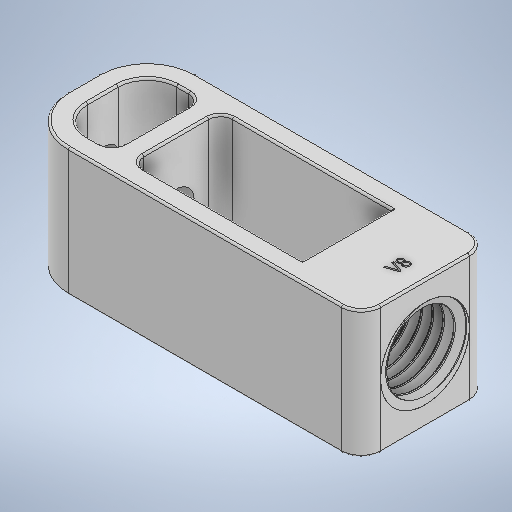
# Autodesk Inventor part: water_release_V6_noncompliant
Saved by Autodesk Inventor 2025.2 (Build 292293000, 293)
## iProperties
Created: 2025-09-30
Part Number: water_release_V6_noncompliant
Material: Generic
Document SubType Name: Modeling
Designer: Eden Salzig
Density: 1 g/cm^3
Appearance: Default
Author: Eden Salzig
Autodesk Inventor part; units mm, degrees
ref_plane "YZ Plane" through (0, 0, 0) normal (1, 0, 0) x (0, 1, 0)
ref_plane "XZ Plane" through (0, 0, 0) normal (0, 1, 0) x (-1, 0, 0)
ref_plane "XY Plane" through (0, 0, 0) normal (0, 0, 1) x (1, 0, 0)
sketch "Sketch1" plane through (0, 0, 0) normal (0, 1, 0) x (-1, 0, 0)
  line L0 (44.45, 0) -> (44.45, -23.114)
  line L1 (49.53, 0) -> (49.53, -23.114)
  arc A0 (55.88, -28.194) -> (68.58, -15.494) centre (55.88, -15.494) ccw
  line L2 (68.58, -7.62) -> (68.58, -15.494)
  arc A1 (68.58, -7.62) -> (55.88, 5.08) centre (55.88, -7.62) ccw
  line L3 (0, 0) -> (49.53, 0)
  line L4 (49.53, -23.114) -> (0, -23.114)
  line L5 (55.88, 5.08) -> (-20.32, 5.08)
  line L6 (-20.32, -28.194) -> (55.88, -28.194)
  line L7 (-20.32, 5.08) -> (-20.32, -28.194)
  line L8 (68.58, -11.557) -> (-20.32, -11.557) construction
  line L9 (0, 0) -> (0, -23.114)
  line L10 (63.5, -15.494) -> (63.5, -7.62)
  line L11 (49.53, -23.114) -> (55.88, -23.114)
  line L12 (49.53, 0) -> (55.88, 0)
  arc A2 (55.88, -23.114) -> (63.5, -15.494) centre (55.88, -15.494) ccw
  arc A3 (63.5, -7.62) -> (55.88, 0) centre (55.88, -7.62) ccw
  dimension "d1" = 24.13
  dimension "d2" = 5.08
  dimension "d3" = 12.7
  dimension "d4" = 12.7
  dimension "d5" = 23.114
  dimension "d6" = 5.08
  dimension "d7" = 5.08
  dimension "d8" = 20.32
  dimension "d63" = 69.85
  dimension "d90" = 5.08
  constraints: 27 end point, 8 point on circle, 6 tangent, 4 centre point, 4 horizontal, 2 horizontal alignment, 2 midpoint, 2 parallel, 2 point on line, 2 vertical, 2 vertical alignment, 1 coincident
  measures "d1" distance between parallel lines of L2 L0
  measures "d2" distance between parallel lines of L1 L0
  measures "d3" radius of A0
  measures "d4" radius of A1
  measures "d5" distance of L9.start L9.end
  measures "d6" distance between parallel lines of L6 L4
  measures "d7" distance between parallel lines of L5 L3
  measures "d8" distance between parallel lines of L7 L9
  measures "d63" distance between parallel lines of L1 L7
  measures "d90" distance between parallel lines of L10 L2
extrude "Extrusion1" add sketch "Sketch1" along normal blind 33.274 contours L3 L1 L4 L0 | L6 L7 L5 A1 L2 A0
sketch "Sketch2" plane through (20.32, 0, 5.08) normal (1, 0, 0) x (0, 0, -1)
  circle A0 centre (16.637, 16.637) radius 11.557
  line L0 (0, 0) -> (0, 33.274) projected
  line L1 (0, 0) -> (33.274, 0) projected
  point P0 (5.08, 0)
  dimension "d12" = 23.114
  dimension "d13" = 16.637
  dimension "d14" = 16.637
  constraints: 1 centre point
  measures "d12" diameter of A0
  measures "d13" distance from line of L0 A0.centre
  measures "d14" distance from line of L1 A0.centre
extrude "Extrusion2" cut sketch "Sketch2" against normal blind 20.32
sketch "Sketch5" plane through (-68.58, 0, -15.494) normal (-1, 0, 0) x (0, 0, 1)
  circle A0 centre (3.937, 16.637) radius 4.699
  line L0 (0, 33.274) -> (7.874, 33.274) projected
  line L1 (-12.7, 0) -> (-12.7, 33.274) projected
  point P0 (15.494, 0)
  point P1 (-12.7, 16.637)
  dimension "d39" = 9.398
  dimension "d40" = 16.637
  dimension "d41" = 16.637
  constraints: 1 centre point, 1 midpoint
  measures "d39" diameter of A0
  measures "d40" distance from line of L0 A0.centre
  measures "d41" distance of point (-12.7, 16.637) A0.centre
extrude "Extrusion3" cut sketch "Sketch5" against normal blind 25.4
fillet "Fillet2" radius 3.175 4 edges at (-44.45, 16.637, 0) (-44.45, 16.637, -23.114) (-49.53, 16.637, 0) (-49.53, 16.637, -23.114)
fillet "Fillet2" radius 5.08 2 edges at (20.32, 16.637, 5.08) (20.32, 16.637, -28.194)
thread "Thread7" size "15/16-9 UNC" class "2B" standard "ANSI Unified Screw Threads" length 20.32
sketch "Sketch17" plane through (0, 16.637, -11.557) normal (0, 1, 0) x (0, 0, 1)
  line L0 (11.557, 0) -> (11.557, 20.32)
  line L1 (11.557, 20.32) -> (9.4644, 20.32)
  line L2 (9.4644, 20.32) -> (9.4644, 0)
  line L3 (9.4644, 0) -> (11.557, 0)
  line L4 (0, -86.3628) -> (0, 38.1005) projected
  constraints: 8 end point
revolve "Revolution7" add sketch "Sketch17" angle 360 about axis through (0, 16.637, -11.557) along (1, 0, 0) separate body
sketch "Sketch16" plane through (0, 16.637, 0) normal (0, -1, 0) x (1, 0, 0)
  line L0 (-1.6464, -0.1429) -> (-1.4112, -0.1429) construction
  line L1 (0.2351, -1.95) -> (-0.0001, -2.4018) construction
  line L2 (-2.8223, -2.4018) -> (-3.0575, -1.95) construction
  line L3 (-1.176, -0.1429) -> (-1.4112, 0.3089) construction
  line L4 (-1.4112, 0.3089) -> (-1.6464, -0.1429) construction
  line L5 (-2.8223, -2.4018) -> (-2.5871, -1.95) construction
  line L6 (-1.176, -0.1429) -> (-0.2353, -1.95)
  line L7 (-3.0575, -1.95) -> (-2.5871, -1.95) construction
  arc A0 (-3.0575, -1.95) -> (-2.8223, -2.0927) centre (-2.8223, -1.8276) ccw construction
  line L8 (0.2351, -1.95) -> (-0.2353, -1.95) construction
  line L9 (-2.8223, -2.4018) -> (-2.8223, -1.95) construction
  line L10 (-0.0001, -2.4018) -> (-0.0001, -1.95) construction
  line L11 (-1.4112, 0.3089) -> (-1.4112, -0.0002) construction
  line L12 (-2.8223, -2.0927) -> (-0.0001, -2.0927)
  arc A1 (-2.8223, -2.0927) -> (-2.5871, -1.95) centre (-2.8223, -1.8276) ccw
  line L13 (-0.2353, -1.95) -> (-0.0001, -2.4018) construction
  line L14 (-2.5871, -1.95) -> (-1.6464, -0.1429)
  line L15 (-0.0001, -0.0002) -> (-0.0001, 0.0177)
  line L16 (-0.0001, 0.0177) -> (-0.0001, -0.0002)
  line L17 (-0.0001, -0.0002) -> (0.0334, -0.0002)
  arc A2 (-0.2353, -1.95) -> (-0.0001, -2.0927) centre (-0.0001, -1.8276) ccw
  arc A3 (-0.0001, -2.0927) -> (0.2351, -1.95) centre (-0.0001, -1.8276) ccw construction
  arc A4 (-1.4112, -0.0002) -> (-1.6464, -0.1429) centre (-1.4112, -0.2653) ccw
  arc A5 (-1.176, -0.1429) -> (-1.4112, -0.0002) centre (-1.4112, -0.2653) ccw
  line L18 (-1.4112, -0.0002) -> (-1.4112, -0.1429) construction
  line L19 (-1.4112, -0.1429) -> (-1.176, -0.1429) construction
  dimension "d151" = 55
  dimension "d152" = 0.4518
  dimension "d153" = 0.4518
  dimension "Sketch16_ThreadOffset" = 0
  dimension "Sketch16_MajorRadius" = 2.0926
  dimension "d156" = 2.8222
  dimension "Sketch16_MinorRadius" = 0
  constraints: 40 end point, 12 point on circle, 10 parallel, 8 tangent, 6 centre point, 6 collinear, 2 midpoint, 2 point on line, 1 horizontal, 1 perpendicular, 3 other
  measures "d151" angle of L6 L14
  measures "d152" distance of L3.end L0.end
  measures "d153" distance of L1.end L10.end
  measures "Sketch16_ThreadOffset" distance between parallel lines of L15 L10
  measures "Sketch16_MajorRadius" distance from line of L12 L15.start
  measures "d156" distance from line of L1.end L9
  measures "Sketch16_MinorRadius" distance edge to line of A5 L17
coil "Coil7" sketch "Sketch16" operation cut axis through (0, 16.637, -11.557) along (1, 0, 0) pitch 2.825 turns 9.190809 hand right bodies 2
fillet "Fillet3" radius 0.508 44 edges at (-64.8603, 33.274, -24.4743) (-68.58, 33.274, -11.557) (-64.8603, 33.274, 1.3603) (-20.32, 33.274, 5.08) (18.8321, 33.274, 3.5921) (20.32, 33.274, -11.557) (18.8321, 33.274, -26.7061) (-20.32, 33.274, -28.194) (-50.4599, 33.274, -0.9299) (-54.2925, 33.274, 0) (-61.2682, 33.274, -2.2318) (-63.5, 33.274, -11.557) (-61.2682, 33.274, -20.8822) (-54.2925, 33.274, -23.114) (-50.4599, 33.274, -22.1841) (-49.53, 33.274, -11.557) (-43.5201, 33.274, -22.1841) (-20.6376, 33.274, -23.114) (-43.5201, 33.274, -0.9299) (-20.6376, 33.274, 0) (-44.45, 33.274, -11.557) (0, 33.274, -11.557) (-43.5201, 0, -0.9299) (-44.45, 0, -11.557) (-43.5201, 0, -22.1841) (-20.6376, 0, -23.114) (-20.6376, 0, 0) (0, 0, -11.557) (18.8321, 0, 3.5921) (20.32, 0, -11.557) (18.8321, 0, -26.7061) (-20.32, 0, -28.194) (-64.8603, 0, -24.4743) (-68.58, 0, -11.557) (-64.8603, 0, 1.3603) (-20.32, 0, 5.08) (-54.2925, 0, 0) (-61.2682, 0, -2.2318) (-63.5, 0, -11.557) (-61.2682, 0, -20.8822) (-54.2925, 0, -23.114) (-50.4599, 0, -22.1841) (-49.53, 0, -11.557) (-50.4599, 0, -0.9299)
sketch "Sketch18" plane through (0, 33.274, 0) normal (0, 1, 0) x (1, 0, 0)
  line L0 (12.065, 9.017) -> (12.065, 14.097) construction
  line L1 (12.065, 14.097) -> (15.24, 14.097) construction
  line L2 (15.24, 14.097) -> (15.24, 9.017) construction
  line L3 (15.24, 9.017) -> (12.065, 9.017) construction
  line L4 (20.32, 0) -> (20.32, 23.114) projected
  line L5 (0, 23.114) -> (0, 0) projected
  line L6 (12.1342, 11.5364) -> (15.1822, 10.4867)
  line L7 (15.1822, 10.4867) -> (15.1822, 10.0495)
  line L8 (15.1822, 10.0495) -> (12.1342, 8.9997)
  line L9 (12.1342, 8.9997) -> (12.1342, 9.4344)
  line L10 (12.1342, 9.4344) -> (14.6659, 10.2792)
  line L11 (14.6659, 10.2792) -> (12.1342, 11.1239)
  line L12 (12.1342, 11.1239) -> (12.1342, 11.5364)
  spline S0 degree 2 poles (15.2513, 12.6627) (15.2513, 12.4355) (15.1155, 12.0625) (14.9895, 11.9316) knots 0 0 0 1 2 2 2
  spline S1 degree 2 poles (14.9895, 11.9316) (14.866, 11.8032) (14.5301, 11.6698) (14.3399, 11.6698) knots 0 0 0 1 2 2 2
  spline S2 degree 2 poles (14.3399, 11.6698) (14.0929, 11.6698) (13.6779, 11.9341) (13.5544, 12.186) knots 0 0 0 1 2 2 2
  line L13 (13.5544, 12.186) -> (13.5421, 12.186)
  spline S3 degree 2 poles (13.5421, 12.186) (13.4112, 11.9613) (13.0999, 11.7439) (12.8678, 11.7439) knots 0 0 0 1 2 2 2
  spline S4 degree 2 poles (12.8678, 11.7439) (12.5244, 11.7439) (12.065, 12.2626) (12.065, 12.6627) knots 0 0 0 1 2 2 2
  spline S5 degree 2 poles (12.065, 12.6627) (12.065, 13.0777) (12.4997, 13.5791) (12.8406, 13.5791) knots 0 0 0 1 2 2 2
  spline S6 degree 2 poles (12.8406, 13.5791) (13.0456, 13.5791) (13.4457, 13.3395) (13.5594, 13.1148) knots 0 0 0 1 2 2 2
  line L14 (13.5594, 13.1148) -> (13.5717, 13.1148)
  spline S7 degree 2 poles (13.5717, 13.1148) (13.6952, 13.3815) (14.0509, 13.6557) (14.3325, 13.6557) knots 0 0 0 1 2 2 2
  spline S8 degree 2 poles (14.3325, 13.6557) (14.7227, 13.6557) (15.2513, 13.0876) (15.2513, 12.6627) knots 0 0 0 1 2 2 2
  spline S9 degree 2 poles (14.372, 13.2358) (14.1843, 13.2358) (13.962, 13.0876) (13.8484, 12.8776) knots 0 0 0 1 2 2 2
  spline S10 degree 2 poles (13.8484, 12.8776) (13.8088, 12.8085) (13.7174, 12.5763) (13.6582, 12.4306) knots 0 0 0 1 2 2 2
  spline S11 degree 2 poles (13.6582, 12.4306) (13.7693, 12.2626) (14.1003, 12.0823) (14.3102, 12.0823) knots 0 0 0 1 2 2 2
  spline S12 degree 2 poles (14.3102, 12.0823) (14.5869, 12.0823) (14.9475, 12.4157) (14.9475, 12.6677) knots 0 0 0 1 2 2 2
  spline S13 degree 2 poles (14.9475, 12.6677) (14.9475, 12.9246) (14.6388, 13.2358) (14.372, 13.2358) knots 0 0 0 1 2 2 2
  spline S14 degree 2 poles (12.8455, 13.179) (12.6405, 13.179) (12.3663, 12.9048) (12.3663, 12.6603) knots 0 0 0 1 2 2 2
  spline S15 degree 2 poles (12.3663, 12.6603) (12.3663, 12.438) (12.6109, 12.1539) (12.8208, 12.1539) knots 0 0 0 1 2 2 2
  spline S16 degree 2 poles (12.8208, 12.1539) (12.9715, 12.1539) (13.1814, 12.2997) (13.2654, 12.4454) knots 0 0 0 1 2 2 2
  spline S17 degree 2 poles (13.2654, 12.4454) (13.3, 12.5071) (13.421, 12.769) (13.4556, 12.8752) knots 0 0 0 1 2 2 2
  spline S18 degree 2 poles (13.4556, 12.8752) (13.3198, 13.053) (13.0308, 13.179) (12.8455, 13.179) knots 0 0 0 1 2 2 2
  point P0 (12.065, 11.557)
  point P1 (0, 11.557)
  dimension "d170" = 3.175
  dimension "d171" = 5.08
  dimension "d172" = 5.08
  constraints: 2 midpoint, 1 horizontal alignment, 2 other
  measures "d170" distance of L0.end L1.end
  measures "d171" distance of L1.end L2.end
  measures "d172" distance between parallel lines of L4 L2
emboss "Emboss1" sketch "Sketch18" operation cut depth 2.54 direction (0, -1, 0)
equation "\"d151\" = d158"
equation "\"d152\" = 0.160083 * Sketch16_Pitch"
equation "\"d153\" = 0.160083 * Sketch16_Pitch"
equation "\"d156\" = Sketch16_Pitch"
equation "\"d26\" = 55deg"
equation "\"Sketch3_Pitch\" = 1.81429"
equation "\"d52\" = 55deg"
equation "\"Sketch6_Pitch\" = 1.81429"
equation "\"d75\" = 55deg"
equation "\"Sketch8_Pitch\" = 3.175"
equation "\"d100\" = 55deg"
equation "\"Sketch10_Pitch\" = 2.54"
equation "\"d120\" = 55deg"
equation "\"Sketch12_Pitch\" = 2.82222"
equation "\"d140\" = 55deg"
equation "\"Sketch14_Pitch\" = 2.82222"
equation "\"d158\" = 55deg"
equation "\"Sketch16_Pitch\" = 2.82222"
body "Solid1"
body "Solid8"
